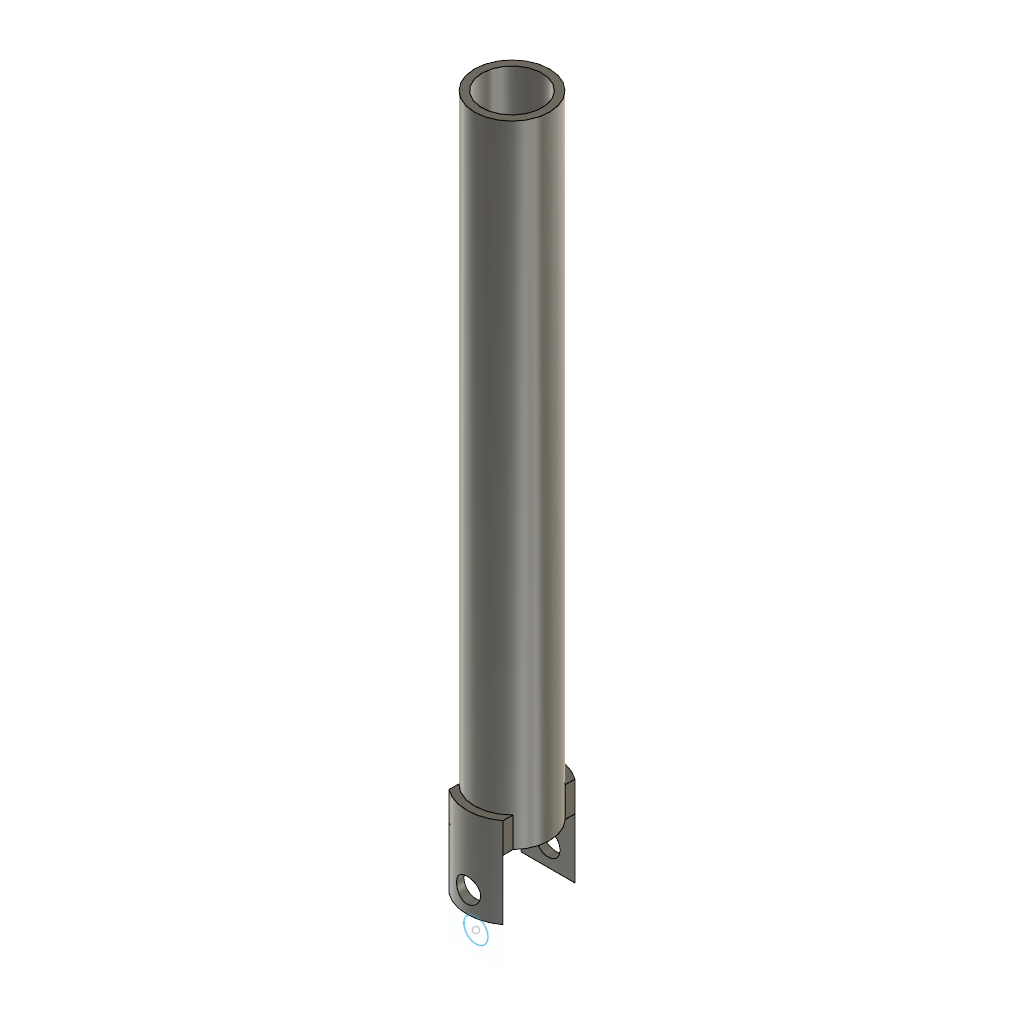
Link2 (Autodesk Fusion 360 design; units mm, degrees)
Autodesk Fusion 360 part; units mm, degrees
sketch "Szkic1" plane through (0, 0, 0) normal (0, 0, 1) x (1, 0, 0)
  circle A0 centre (0, 0) radius 12.5
  circle A1 centre (0, 0) radius 10
  dimension "d1" = 25
  dimension "d2" = 20
  constraint coincident A0.centre A1.centre
  constraint concentric A0 A1
  measures "d1" diameter of A0
  measures "d2" diameter of A1
extrude "Wyciągnięcie proste1" add sketch "Szkic1" along normal blind 210
sketch "Szkic2" plane through (0, 0, 0) normal (0, 0, 1) x (1, 0, 0)
  line L0 (9, 12) -> (-9, 12)
  line L1 (-9, -12) -> (9, -12)
  line L2 (1.75, 0) -> (22.5, 0)
  arc A0 (9, 12) -> (-9, 12) centre (0, 0) ccw
  arc A1 (-9, -12) -> (9, -12) centre (0, 0) ccw
  dimension "d5" = 30
  dimension "d7" = 9
  constraint coincident A0.centre A1.centre
  constraint horizontal L0
  constraint horizontal L1
  constraint symmetric L0 L1 L2
  constraint concentric A0 A1
  constraint equal A0 A1
  measures "d5" diameter of A0
  measures "d7" horizontal distance of A0.centre L1.end
extrude "Wyciągnięcie proste2" add sketch "Szkic2" along normal blind -20 and the other way blind -10
sketch "Szkic3" plane through (0, 0, 0) normal (0, 0, 1) x (1, 0, 0)
  line L0 (-9, -12) -> (-9, -7)
  line L1 (-9, -7) -> (-2, -12)
  line L2 (9, -12) -> (9, -7.3336)
  line L3 (9, -7.3336) -> (1, -12)
  line L4 (-9, 12) -> (-9, 7)
  line L5 (-9, 7) -> (-2.515, 12)
  line L6 (9, 12) -> (9, 7)
  line L7 (9, 7) -> (2.435, 12)
  line L8 (-9, 12) -> (-2.515, 12)
  line L9 (2.435, 12) -> (9, 12)
  line L10 (1, -12) -> (9, -12)
  line L11 (-2, -12) -> (-9, -12)
  constraint vertical L0
  constraint vertical L2
  constraint vertical L4
  constraint vertical L6
  constraint perpendicular L4 L8
  constraint perpendicular L6 L9
  constraint perpendicular L2 L10
  constraint perpendicular L0 L11
extrude "Wyciągnięcie proste3" add sketch "Szkic3" along normal blind 10
sketch "Szkic4" plane through (0, -12, 0) normal (0, 1, 0) x (-1, 0, 0)
  line L0 (9, 0) -> (-9, 0)
  line L1 (-9, 0) -> (-9, -20)
  line L2 (-9, -20) -> (9, -20)
  line L3 (9, -20) -> (9, 0)
  circle A0 centre (0, -13) radius 4
  dimension "d12" = 8
  measures "d12" diameter of A0
extrude "Wyciągnięcie proste4" cut sketch "Szkic4" along normal blind 35 and the other way blind 10 contours A0
move_body "Przesuń1" bodies 1 to x (1, 0, 0) y (0, 1, 0) z (0, 0, 1) at (0, 0, 13)
